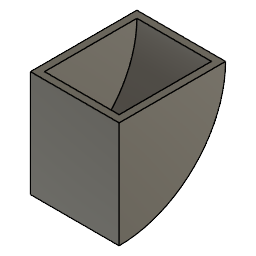
Dumper Small (Autodesk Fusion 360 design; units mm, degrees)
Autodesk Fusion 360 part; units mm, degrees
sketch "Sketch1" plane through (0, 0, 0) normal (1, 0, 0) x (0, 1, 0)
  line L0 (0, 0) -> (0, 76.2)
  line L1 (0, 76.2) -> (76.2, 76.2)
  arc A0 (0, 0) -> (76.2, 76.2) centre (0, 76.2) ccw
  dimension "d1" = 76.2
  dimension "d2" = 76.2
  constraint coincident L0.start A0.start
  constraint vertical L0
  constraint perpendicular L0 L1
  measures "d1" distance of L0.start L0.end
  measures "d2" distance of L0.end L1.end
extrude "Extrude1" add sketch "Sketch1" along normal blind 63.5
shell "Shell1" thickness 5.08 removed faces 1 at (21.1667, 25.4, 76.2)
